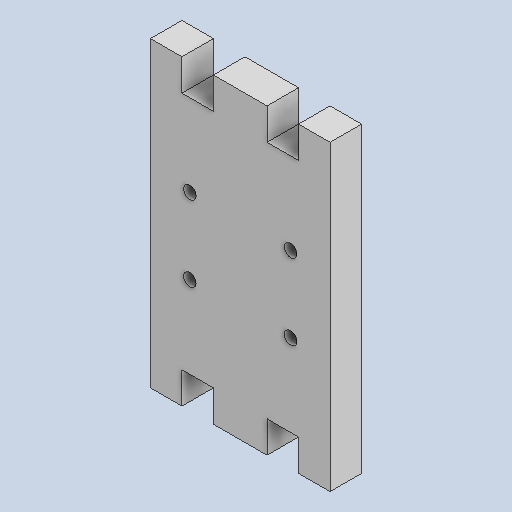
# Autodesk Inventor part: KneeL
Saved by Autodesk Inventor 2025.2 (Build 292293000, 293)
## iProperties
Created: 2025-06-23
Part Number: KneeL
Material: Generic
Document SubType Name: Modeling
Designer: ricoa
Density: 1 g/cm^3
Appearance: Default
Author: ricoa
Autodesk Inventor part; units mm, degrees
ref_plane "YZ Plane" through (0, 0, 0) normal (1, 0, 0) x (0, 1, 0)
ref_plane "XZ Plane" through (0, 0, 0) normal (0, 1, 0) x (-1, 0, 0)
ref_plane "XY Plane" through (0, 0, 0) normal (0, 0, 1) x (1, 0, 0)
sketch "Sketch1" plane through (0, 0, 0) normal (0, 0, 1) x (1, 0, 0)
  line L0 (1.4505, 4.2174) -> (1.4505, 4.1666) projected
  line L1 (1.4505, -29.7808) -> (1.4505, -29.8316) projected
  circle A0 centre (22.25, -14.5) radius 1 projected
  circle A1 centre (6.25, -14.5) radius 1 projected
  circle A2 centre (6.25, -2.5) radius 1 projected
  circle A3 centre (22.25, -2.5) radius 1 projected
  line L2 (28.5, -17) -> (28.5, -25.25) projected
  line L3 (28.25, -25.5) -> (26.3964, -25.5) projected
  line L4 (28.5, 8.25) -> (28.5, 0.25) projected
  line L5 (26.3964, 8.5) -> (28.25, 8.5) projected
  line L6 (0, 0.25) -> (0, 8.25) projected
  line L7 (0.25, 8.5) -> (2.1036, 8.5) projected
  line L8 (0, -25.25) -> (0, -17) projected
  line L9 (2.1036, -25.5) -> (0.25, -25.5) projected
  line L10 (28.5, -25.5) -> (28.5, 8.5)
  line L11 (0, 8.5) -> (0, -25.5)
  line L12 (0, -8.5) -> (28.5, -8.5) construction
  line L13 (14.25, -25.5) -> (14.25, 8.5) construction
  line L14 (28.5, -25.5) -> (28.5, -32.5)
  line L15 (28.5, -32.5) -> (23.5, -32.5)
  line L16 (23.5, -32.5) -> (23.5, -27.5)
  line L17 (23.5, -27.5) -> (18.5, -27.5)
  line L18 (18.5, -27.5) -> (18.5, -32.5)
  line L19 (18.5, -32.5) -> (10, -32.5)
  line L20 (10, -32.5) -> (10, -27.5)
  line L21 (10, -27.5) -> (5, -27.5)
  line L22 (5, -27.5) -> (5, -32.5)
  line L23 (5, -32.5) -> (0, -32.5)
  line L24 (0, -32.5) -> (0, -25.5)
  line L25 (1.4505, 12.7808) -> (1.4505, 12.8316)
  line L26 (28.5, 0) -> (28.5, 8.25)
  line L27 (28.25, 8.5) -> (26.3964, 8.5)
  line L28 (0, 8.25) -> (0, 0)
  line L29 (2.1036, 8.5) -> (0.25, 8.5)
  line L30 (14.25, 8.5) -> (14.25, -25.5) construction
  line L31 (28.5, 8.5) -> (28.5, 15.5)
  line L32 (28.5, 15.5) -> (23.5, 15.5)
  line L33 (23.5, 15.5) -> (23.5, 10.5)
  line L34 (23.5, 10.5) -> (18.5, 10.5)
  line L35 (18.5, 10.5) -> (18.5, 15.5)
  line L36 (18.5, 15.5) -> (10, 15.5)
  line L37 (10, 15.5) -> (10, 10.5)
  line L38 (10, 10.5) -> (5, 10.5)
  line L39 (5, 10.5) -> (5, 15.5)
  line L40 (5, 15.5) -> (0, 15.5)
  line L41 (0, 15.5) -> (0, 8.5)
  point P0 (0, 0)
  dimension "d5" = 34
  dimension "d6" = 7
  dimension "d7" = 5
  constraints: 64 end point, 16 symmetric about line, 12 point on line, 7 perpendicular, 2 midpoint, 1 parallel, 1 vertical, 1 other
  measures "d5" distance of L10.start L10.end
  measures "d6" distance of L10.start L14.end
  measures "d7" distance of L15.end L16.end
extrude "Extrusion1" add sketch "Sketch1" along normal blind 5
body "Solid1"
